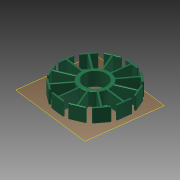
# Autodesk Inventor part: Stator
Saved by Autodesk Inventor 2013 (Build 170138000, 138)
## iProperties
Created: 2013-09-29
Part Number: Stator
Material: Generic
Document SubType Name: Modeling
Designer: Hunter
Density: 1 g/cm^3
Author: Hunter
Autodesk Inventor part; units mm, degrees
ref_plane "YZ Plane" through (0, 0, 0) normal (1, 0, 0) x (0, 1, 0)
ref_plane "XZ Plane" through (0, 0, 0) normal (0, 1, 0) x (-1, 0, 0)
ref_plane "XY Plane" through (0, 0, 0) normal (0, 0, 1) x (1, 0, 0)
ref_plane "Work Plane1" through (0, 0, 2) normal (0, 0, 1) x (0.9888023, -0.1492311, 0)
sketch "Sketch1" plane through (0, 0, 2) normal (0, 0, 1) x (0.9888023, -0.1492311, 0)
  line L0 (19.2713, -4) -> (19.8258, -4)
  line L1 (19.8258, 4) -> (19.2713, 4)
  line L2 (19.0213, 3.75) -> (19.0213, 0.75)
  line L3 (19.0213, -0.75) -> (19.0213, -3.75)
  arc A0 (18.7713, 0.5) -> (19.0213, 0.75) centre (18.7713, 0.75) ccw
  arc A1 (19.0213, -0.75) -> (18.7713, -0.5) centre (18.7713, -0.75) ccw
  arc A2 (19.0213, -3.75) -> (19.2713, -4) centre (19.2713, -3.75) ccw
  arc A3 (19.2713, 4) -> (19.0213, 3.75) centre (19.2713, 3.75) ccw
  circle A4 centre (0, 0) radius 6.5 projected
  arc A5 (8.4687, 0.7286) -> (7.6984, 3.6034) centre (0, 0) ccw
  arc A6 (20.0688, -3.8087) -> (20.0688, 3.8087) centre (4.2947, 0) ccw
  arc A7 (20.0688, 3.8087) -> (19.8258, 4) centre (19.8258, 3.75) ccw
  arc A8 (19.8258, -4) -> (20.0688, -3.8087) centre (19.8258, -3.75) ccw
  line L4 (18.7713, 0.5) -> (8.7178, 0.5)
  line L5 (18.7713, -0.5) -> (8.7178, -0.5)
  arc A9 (8.4687, 0.7286) -> (8.7178, 0.5) centre (8.7178, 0.75) ccw
  arc A10 (8.7178, -0.5) -> (8.4687, -0.7286) centre (8.7178, -0.75) ccw
  line L6 (18.6895, 6.1716) -> (19.1696, 6.4488)
  line L7 (15.1696, 13.377) -> (14.6895, 13.0998)
  line L8 (14.598, 12.7583) -> (16.098, 10.1602)
  line L9 (16.848, 8.8612) -> (18.348, 6.2631)
  arc A11 (16.0065, 9.8187) -> (16.098, 10.1602) centre (15.8815, 10.0352) ccw
  arc A12 (16.848, 8.8612) -> (16.5065, 8.9527) centre (16.6315, 8.7362) ccw
  arc A13 (18.348, 6.2631) -> (18.6895, 6.1716) centre (18.5645, 6.3881) ccw
  arc A14 (14.6895, 13.0998) -> (14.598, 12.7583) centre (14.8145, 12.8833) ccw
  arc A15 (6.9698, 4.8653) -> (4.8653, 6.9698) centre (0, 0) ccw
  arc A16 (19.2844, 6.736) -> (15.4757, 13.3328) centre (3.7193, 2.1473) ccw
  arc A17 (15.4757, 13.3328) -> (15.1696, 13.377) centre (15.2946, 13.1605) ccw
  arc A18 (19.1696, 6.4488) -> (19.2844, 6.736) centre (19.0446, 6.6653) ccw
  line L10 (16.0065, 9.8187) -> (7.2998, 4.7919)
  line L11 (16.5065, 8.9527) -> (7.7998, 3.9259)
  arc A19 (6.9698, 4.8653) -> (7.2998, 4.7919) centre (7.1748, 5.0084) ccw
  arc A20 (7.7998, 3.9259) -> (7.6984, 3.6034) centre (7.9248, 3.7094) ccw
  line L12 (13.0998, 14.6895) -> (13.377, 15.1696)
  line L13 (6.4488, 19.1696) -> (6.1716, 18.6895)
  line L14 (6.2631, 18.348) -> (8.8612, 16.848)
  line L15 (10.1602, 16.098) -> (12.7583, 14.598)
  arc A21 (8.9527, 16.5065) -> (8.8612, 16.848) centre (8.7362, 16.6315) ccw
  arc A22 (10.1602, 16.098) -> (9.8187, 16.0065) centre (10.0352, 15.8815) ccw
  arc A23 (12.7583, 14.598) -> (13.0998, 14.6895) centre (12.8833, 14.8145) ccw
  arc A24 (6.1716, 18.6895) -> (6.2631, 18.348) centre (6.3881, 18.5645) ccw
  arc A25 (3.6034, 7.6984) -> (0.7286, 8.4687) centre (0, 0) ccw
  arc A26 (13.3328, 15.4757) -> (6.736, 19.2844) centre (2.1473, 3.7193) ccw
  arc A27 (6.736, 19.2844) -> (6.4488, 19.1696) centre (6.6653, 19.0446) ccw
  arc A28 (13.377, 15.1696) -> (13.3328, 15.4757) centre (13.1605, 15.2946) ccw
  line L16 (8.9527, 16.5065) -> (3.9259, 7.7998)
  line L17 (9.8187, 16.0065) -> (4.7919, 7.2998)
  arc A29 (3.6034, 7.6984) -> (3.9259, 7.7998) centre (3.7094, 7.9248) ccw
  arc A30 (4.7919, 7.2998) -> (4.8653, 6.9698) centre (5.0084, 7.1748) ccw
  line L18 (4, 19.2713) -> (4, 19.8258)
  line L19 (-4, 19.8258) -> (-4, 19.2713)
  line L20 (-3.75, 19.0213) -> (-0.75, 19.0213)
  line L21 (0.75, 19.0213) -> (3.75, 19.0213)
  arc A31 (-0.5, 18.7713) -> (-0.75, 19.0213) centre (-0.75, 18.7713) ccw
  arc A32 (0.75, 19.0213) -> (0.5, 18.7713) centre (0.75, 18.7713) ccw
  arc A33 (3.75, 19.0213) -> (4, 19.2713) centre (3.75, 19.2713) ccw
  arc A34 (-4, 19.2713) -> (-3.75, 19.0213) centre (-3.75, 19.2713) ccw
  arc A35 (-0.7286, 8.4687) -> (-3.6034, 7.6984) centre (0, 0) ccw
  arc A36 (3.8087, 20.0688) -> (-3.8087, 20.0688) centre (0, 4.2947) ccw
  arc A37 (-3.8087, 20.0688) -> (-4, 19.8258) centre (-3.75, 19.8258) ccw
  arc A38 (4, 19.8258) -> (3.8087, 20.0688) centre (3.75, 19.8258) ccw
  line L22 (-0.5, 18.7713) -> (-0.5, 8.7178)
  line L23 (0.5, 18.7713) -> (0.5, 8.7178)
  arc A39 (-0.7286, 8.4687) -> (-0.5, 8.7178) centre (-0.75, 8.7178) ccw
  arc A40 (0.5, 8.7178) -> (0.7286, 8.4687) centre (0.75, 8.7178) ccw
  line L24 (-6.1716, 18.6895) -> (-6.4488, 19.1696)
  line L25 (-13.377, 15.1696) -> (-13.0998, 14.6895)
  line L26 (-12.7583, 14.598) -> (-10.1602, 16.098)
  line L27 (-8.8612, 16.848) -> (-6.2631, 18.348)
  arc A41 (-9.8187, 16.0065) -> (-10.1602, 16.098) centre (-10.0352, 15.8815) ccw
  arc A42 (-8.8612, 16.848) -> (-8.9527, 16.5065) centre (-8.7362, 16.6315) ccw
  arc A43 (-6.2631, 18.348) -> (-6.1716, 18.6895) centre (-6.3881, 18.5645) ccw
  arc A44 (-13.0998, 14.6895) -> (-12.7583, 14.598) centre (-12.8833, 14.8145) ccw
  arc A45 (-4.8653, 6.9698) -> (-6.9698, 4.8653) centre (0, 0) ccw
  arc A46 (-6.736, 19.2844) -> (-13.3328, 15.4757) centre (-2.1473, 3.7193) ccw
  arc A47 (-13.3328, 15.4757) -> (-13.377, 15.1696) centre (-13.1605, 15.2946) ccw
  arc A48 (-6.4488, 19.1696) -> (-6.736, 19.2844) centre (-6.6653, 19.0446) ccw
  line L28 (-9.8187, 16.0065) -> (-4.7919, 7.2998)
  line L29 (-8.9527, 16.5065) -> (-3.9259, 7.7998)
  arc A49 (-4.8653, 6.9698) -> (-4.7919, 7.2998) centre (-5.0084, 7.1748) ccw
  arc A50 (-3.9259, 7.7998) -> (-3.6034, 7.6984) centre (-3.7094, 7.9248) ccw
  line L30 (-14.6895, 13.0998) -> (-15.1696, 13.377)
  line L31 (-19.1696, 6.4488) -> (-18.6895, 6.1716)
  line L32 (-18.348, 6.2631) -> (-16.848, 8.8612)
  line L33 (-16.098, 10.1602) -> (-14.598, 12.7583)
  arc A51 (-16.5065, 8.9527) -> (-16.848, 8.8612) centre (-16.6315, 8.7362) ccw
  arc A52 (-16.098, 10.1602) -> (-16.0065, 9.8187) centre (-15.8815, 10.0352) ccw
  arc A53 (-14.598, 12.7583) -> (-14.6895, 13.0998) centre (-14.8145, 12.8833) ccw
  arc A54 (-18.6895, 6.1716) -> (-18.348, 6.2631) centre (-18.5645, 6.3881) ccw
  arc A55 (-7.6984, 3.6034) -> (-8.4687, 0.7286) centre (0, 0) ccw
  arc A56 (-15.4757, 13.3328) -> (-19.2844, 6.736) centre (-3.7193, 2.1473) ccw
  arc A57 (-19.2844, 6.736) -> (-19.1696, 6.4488) centre (-19.0446, 6.6653) ccw
  arc A58 (-15.1696, 13.377) -> (-15.4757, 13.3328) centre (-15.2946, 13.1605) ccw
  line L34 (-16.5065, 8.9527) -> (-7.7998, 3.9259)
  line L35 (-16.0065, 9.8187) -> (-7.2998, 4.7919)
  arc A59 (-7.6984, 3.6034) -> (-7.7998, 3.9259) centre (-7.9248, 3.7094) ccw
  arc A60 (-7.2998, 4.7919) -> (-6.9698, 4.8653) centre (-7.1748, 5.0084) ccw
  line L36 (-19.2713, 4) -> (-19.8258, 4)
  line L37 (-19.8258, -4) -> (-19.2713, -4)
  line L38 (-19.0213, -3.75) -> (-19.0213, -0.75)
  line L39 (-19.0213, 0.75) -> (-19.0213, 3.75)
  arc A61 (-18.7713, -0.5) -> (-19.0213, -0.75) centre (-18.7713, -0.75) ccw
  arc A62 (-19.0213, 0.75) -> (-18.7713, 0.5) centre (-18.7713, 0.75) ccw
  arc A63 (-19.0213, 3.75) -> (-19.2713, 4) centre (-19.2713, 3.75) ccw
  arc A64 (-19.2713, -4) -> (-19.0213, -3.75) centre (-19.2713, -3.75) ccw
  arc A65 (-8.4687, -0.7286) -> (-7.6984, -3.6034) centre (0, 0) ccw
  arc A66 (-20.0688, 3.8087) -> (-20.0688, -3.8087) centre (-4.2947, 0) ccw
  arc A67 (-20.0688, -3.8087) -> (-19.8258, -4) centre (-19.8258, -3.75) ccw
  arc A68 (-19.8258, 4) -> (-20.0688, 3.8087) centre (-19.8258, 3.75) ccw
  line L40 (-18.7713, -0.5) -> (-8.7178, -0.5)
  line L41 (-18.7713, 0.5) -> (-8.7178, 0.5)
  arc A69 (-8.4687, -0.7286) -> (-8.7178, -0.5) centre (-8.7178, -0.75) ccw
  arc A70 (-8.7178, 0.5) -> (-8.4687, 0.7286) centre (-8.7178, 0.75) ccw
  line L42 (-18.6895, -6.1716) -> (-19.1696, -6.4488)
  line L43 (-15.1696, -13.377) -> (-14.6895, -13.0998)
  line L44 (-14.598, -12.7583) -> (-16.098, -10.1602)
  line L45 (-16.848, -8.8612) -> (-18.348, -6.2631)
  arc A71 (-16.0065, -9.8187) -> (-16.098, -10.1602) centre (-15.8815, -10.0352) ccw
  arc A72 (-16.848, -8.8612) -> (-16.5065, -8.9527) centre (-16.6315, -8.7362) ccw
  arc A73 (-18.348, -6.2631) -> (-18.6895, -6.1716) centre (-18.5645, -6.3881) ccw
  arc A74 (-14.6895, -13.0998) -> (-14.598, -12.7583) centre (-14.8145, -12.8833) ccw
  arc A75 (-6.9698, -4.8653) -> (-4.8653, -6.9698) centre (0, 0) ccw
  arc A76 (-19.2844, -6.736) -> (-15.4757, -13.3328) centre (-3.7193, -2.1473) ccw
  arc A77 (-15.4757, -13.3328) -> (-15.1696, -13.377) centre (-15.2946, -13.1605) ccw
  arc A78 (-19.1696, -6.4488) -> (-19.2844, -6.736) centre (-19.0446, -6.6653) ccw
  line L46 (-16.0065, -9.8187) -> (-7.2998, -4.7919)
  line L47 (-16.5065, -8.9527) -> (-7.7998, -3.9259)
  arc A79 (-6.9698, -4.8653) -> (-7.2998, -4.7919) centre (-7.1748, -5.0084) ccw
  arc A80 (-7.7998, -3.9259) -> (-7.6984, -3.6034) centre (-7.9248, -3.7094) ccw
  line L48 (-13.0998, -14.6895) -> (-13.377, -15.1696)
  line L49 (-6.4488, -19.1696) -> (-6.1716, -18.6895)
  line L50 (-6.2631, -18.348) -> (-8.8612, -16.848)
  line L51 (-10.1602, -16.098) -> (-12.7583, -14.598)
  arc A81 (-8.9527, -16.5065) -> (-8.8612, -16.848) centre (-8.7362, -16.6315) ccw
  arc A82 (-10.1602, -16.098) -> (-9.8187, -16.0065) centre (-10.0352, -15.8815) ccw
  arc A83 (-12.7583, -14.598) -> (-13.0998, -14.6895) centre (-12.8833, -14.8145) ccw
  arc A84 (-6.1716, -18.6895) -> (-6.2631, -18.348) centre (-6.3881, -18.5645) ccw
  arc A85 (-3.6034, -7.6984) -> (-0.7286, -8.4687) centre (0, 0) ccw
  arc A86 (-13.3328, -15.4757) -> (-6.736, -19.2844) centre (-2.1473, -3.7193) ccw
  arc A87 (-6.736, -19.2844) -> (-6.4488, -19.1696) centre (-6.6653, -19.0446) ccw
  arc A88 (-13.377, -15.1696) -> (-13.3328, -15.4757) centre (-13.1605, -15.2946) ccw
  line L52 (-8.9527, -16.5065) -> (-3.9259, -7.7998)
  line L53 (-9.8187, -16.0065) -> (-4.7919, -7.2998)
  arc A89 (-3.6034, -7.6984) -> (-3.9259, -7.7998) centre (-3.7094, -7.9248) ccw
  arc A90 (-4.7919, -7.2998) -> (-4.8653, -6.9698) centre (-5.0084, -7.1748) ccw
  line L54 (-4, -19.2713) -> (-4, -19.8258)
  line L55 (4, -19.8258) -> (4, -19.2713)
  line L56 (3.75, -19.0213) -> (0.75, -19.0213)
  line L57 (-0.75, -19.0213) -> (-3.75, -19.0213)
  arc A91 (0.5, -18.7713) -> (0.75, -19.0213) centre (0.75, -18.7713) ccw
  arc A92 (-0.75, -19.0213) -> (-0.5, -18.7713) centre (-0.75, -18.7713) ccw
  arc A93 (-3.75, -19.0213) -> (-4, -19.2713) centre (-3.75, -19.2713) ccw
  arc A94 (4, -19.2713) -> (3.75, -19.0213) centre (3.75, -19.2713) ccw
  arc A95 (0.7286, -8.4687) -> (3.6034, -7.6984) centre (0, 0) ccw
  arc A96 (-3.8087, -20.0688) -> (3.8087, -20.0688) centre (0, -4.2947) ccw
  arc A97 (3.8087, -20.0688) -> (4, -19.8258) centre (3.75, -19.8258) ccw
  arc A98 (-4, -19.8258) -> (-3.8087, -20.0688) centre (-3.75, -19.8258) ccw
  line L58 (0.5, -18.7713) -> (0.5, -8.7178)
  line L59 (-0.5, -18.7713) -> (-0.5, -8.7178)
  arc A99 (0.7286, -8.4687) -> (0.5, -8.7178) centre (0.75, -8.7178) ccw
  arc A100 (-0.5, -8.7178) -> (-0.7286, -8.4687) centre (-0.75, -8.7178) ccw
  line L60 (6.1716, -18.6895) -> (6.4488, -19.1696)
  line L61 (13.377, -15.1696) -> (13.0998, -14.6895)
  line L62 (12.7583, -14.598) -> (10.1602, -16.098)
  line L63 (8.8612, -16.848) -> (6.2631, -18.348)
  arc A101 (9.8187, -16.0065) -> (10.1602, -16.098) centre (10.0352, -15.8815) ccw
  arc A102 (8.8612, -16.848) -> (8.9527, -16.5065) centre (8.7362, -16.6315) ccw
  arc A103 (6.2631, -18.348) -> (6.1716, -18.6895) centre (6.3881, -18.5645) ccw
  arc A104 (13.0998, -14.6895) -> (12.7583, -14.598) centre (12.8833, -14.8145) ccw
  arc A105 (4.8653, -6.9698) -> (6.9698, -4.8653) centre (0, 0) ccw
  arc A106 (6.736, -19.2844) -> (13.3328, -15.4757) centre (2.1473, -3.7193) ccw
  arc A107 (13.3328, -15.4757) -> (13.377, -15.1696) centre (13.1605, -15.2946) ccw
  arc A108 (6.4488, -19.1696) -> (6.736, -19.2844) centre (6.6653, -19.0446) ccw
  line L64 (9.8187, -16.0065) -> (4.7919, -7.2998)
  line L65 (8.9527, -16.5065) -> (3.9259, -7.7998)
  arc A109 (4.8653, -6.9698) -> (4.7919, -7.2998) centre (5.0084, -7.1748) ccw
  arc A110 (3.9259, -7.7998) -> (3.6034, -7.6984) centre (3.7094, -7.9248) ccw
  line L66 (14.6895, -13.0998) -> (15.1696, -13.377)
  line L67 (19.1696, -6.4488) -> (18.6895, -6.1716)
  line L68 (18.348, -6.2631) -> (16.848, -8.8612)
  line L69 (16.098, -10.1602) -> (14.598, -12.7583)
  arc A111 (16.5065, -8.9527) -> (16.848, -8.8612) centre (16.6315, -8.7362) ccw
  arc A112 (16.098, -10.1602) -> (16.0065, -9.8187) centre (15.8815, -10.0352) ccw
  arc A113 (14.598, -12.7583) -> (14.6895, -13.0998) centre (14.8145, -12.8833) ccw
  arc A114 (18.6895, -6.1716) -> (18.348, -6.2631) centre (18.5645, -6.3881) ccw
  arc A115 (7.6984, -3.6034) -> (8.4687, -0.7286) centre (0, 0) ccw
  arc A116 (15.4757, -13.3328) -> (19.2844, -6.736) centre (3.7193, -2.1473) ccw
  arc A117 (19.2844, -6.736) -> (19.1696, -6.4488) centre (19.0446, -6.6653) ccw
  arc A118 (15.1696, -13.377) -> (15.4757, -13.3328) centre (15.2946, -13.1605) ccw
  line L70 (16.5065, -8.9527) -> (7.7998, -3.9259)
  line L71 (16.0065, -9.8187) -> (7.2998, -4.7919)
  arc A119 (7.6984, -3.6034) -> (7.7998, -3.9259) centre (7.9248, -3.7094) ccw
  arc A120 (7.2998, -4.7919) -> (6.9698, -4.8653) centre (7.1748, -5.0084) ccw
  point P0 (20.0213, 4)
  point P1 (20.0213, -4)
  point P2 (19.0213, 4)
  point P3 (19.0213, 0.5)
  point P4 (19.0213, -0.5)
  point P5 (15.339, 13.4748)
  point P6 (19.339, 6.5466)
  point P7 (14.473, 12.9748)
  point P8 (16.223, 9.9437)
  point P9 (16.723, 9.0777)
  point P10 (6.5466, 19.339)
  point P11 (13.4748, 15.339)
  point P12 (6.0466, 18.473)
  point P13 (9.0777, 16.723)
  point P14 (9.9437, 16.223)
  point P15 (-4, 20.0213)
  point P16 (4, 20.0213)
  point P17 (-4, 19.0213)
  point P18 (-0.5, 19.0213)
  point P19 (0.5, 19.0213)
  point P20 (-13.4748, 15.339)
  point P21 (-6.5466, 19.339)
  point P22 (-12.9748, 14.473)
  point P23 (-9.9437, 16.223)
  point P24 (-9.0777, 16.723)
  point P25 (-19.339, 6.5466)
  point P26 (-15.339, 13.4748)
  point P27 (-18.473, 6.0466)
  point P28 (-16.723, 9.0777)
  point P29 (-16.223, 9.9437)
  point P30 (-20.0213, -4)
  point P31 (-20.0213, 4)
  point P32 (-19.0213, -4)
  point P33 (-19.0213, -0.5)
  point P34 (-19.0213, 0.5)
  point P35 (-15.339, -13.4748)
  point P36 (-19.339, -6.5466)
  point P37 (-14.473, -12.9748)
  point P38 (-16.223, -9.9437)
  point P39 (-16.723, -9.0777)
  point P40 (-6.5466, -19.339)
  point P41 (-13.4748, -15.339)
  point P42 (-6.0466, -18.473)
  point P43 (-9.0777, -16.723)
  point P44 (-9.9437, -16.223)
  point P45 (4, -20.0213)
  point P46 (-4, -20.0213)
  point P47 (4, -19.0213)
  point P48 (0.5, -19.0213)
  point P49 (-0.5, -19.0213)
  point P50 (13.4748, -15.339)
  point P51 (6.5466, -19.339)
  point P52 (12.9748, -14.473)
  point P53 (9.9437, -16.223)
  point P54 (9.0777, -16.723)
  point P55 (19.339, -6.5466)
  point P56 (15.339, -13.4748)
  point P57 (18.473, -6.0466)
  point P58 (16.723, -9.0777)
  point P59 (16.223, -9.9437)
  dimension "d3" = 8
  dimension "d5" = 0.25
  dimension "d27" = 0.25
  dimension "d28" = 0.25
  constraints: 264 point on circle, 144 end point, 120 centre point, 72 point on line, 15 tangent, 4 equal radius, 2 parallel, 1 horizontal, 1 perpendicular
  measures "d3" distance of point (20.021, 4) point (20.021, -4)
  measures "d5" radius of A0
  measures "d27" radius of A7
  measures "d28" radius of A9
extrude "Extrusion2" add sketch "Sketch1" along normal blind 8
fillet "Fillet1" radius 0.3 9 edges at (18.6504, -3.3945, 10) (18.4726, -5.0634, 10) (18.2948, -6.7323, 10) (18.7327, -6.8725, 10) (19.9266, 1.038, 10) (19.4668, 1.0333, 10) (19.1441, -0.6138, 10) (18.8215, -2.2608, 10) (8.4467, 0.9501, 10)
fillet "Fillet2" radius 0.3 9 edges at (18.8215, -2.2608, 2) (19.1441, -0.6138, 2) (19.4668, 1.0333, 2) (19.9266, 1.038, 2) (18.7327, -6.8725, 2) (18.2948, -6.7323, 2) (18.4726, -5.0634, 2) (18.6504, -3.3945, 2) (8.4467, 0.9501, 2)
body "Solid2"
